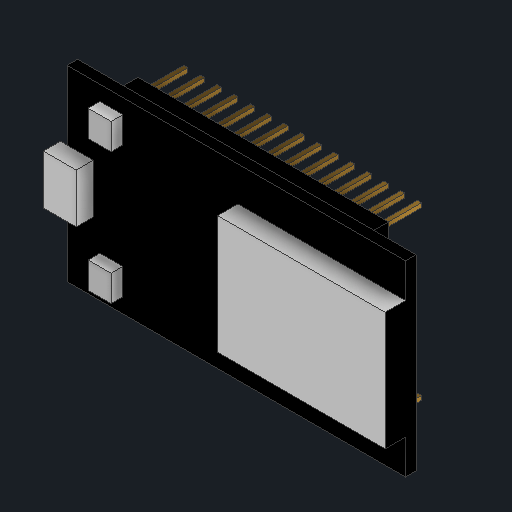
# Autodesk Inventor part: ESP32 DevKit 30-pin (Hosyond)
Saved by Autodesk Inventor 2027.2 (Build 312334000, 334)
## iProperties
Created: 2026-11-06
Part Number: ESP32 DevKit 30-pin (Hosyond)
Material: Generic
Description: Hosyond ESP-WROOM-32 30-pin devkit, simplified envelope (dims assumed, verify)
Document SubType Name: Modeling
Designer: isaac
Density: 1 g/cm^3
Appearance: Default
Author: isaac
Autodesk Inventor part; units mm, degrees
sketch "Sketch1" plane through (0, 0, 0) normal (0, 0, 1) x (1, 0, 0)
  line L0 (0, -14.25) -> (51.5, -14.25)
  line L1 (51.5, -14.25) -> (51.5, 14.25)
  line L2 (51.5, 14.25) -> (0, 14.25)
  line L3 (0, 14.25) -> (0, -14.25)
  constraints: 8 end point, 2 parallel, 1 horizontal, 1 perpendicular
extrude "PCB" add sketch "Sketch1" along normal blind 1.6
ref_plane "Work Plane1" through (0, 0, 1.6) normal (0, 0, 1) x (1, 0, 0)
sketch "Sketch2" plane through (0, 0, 1.6) normal (0, 0, 1) x (1, 0, 0)
  line L0 (26, -9) -> (51.5, -9)
  line L1 (51.5, -9) -> (51.5, 9)
  line L2 (51.5, 9) -> (26, 9)
  line L3 (26, 9) -> (26, -9)
  constraints: 8 end point, 2 parallel, 1 horizontal, 1 perpendicular
extrude "WROOM-32 module" add sketch "Sketch2" along normal blind 3.1
ref_plane "Work Plane2" through (0, 0, 1.6) normal (0, 0, 1) x (1, 0, 0)
sketch "Sketch3" plane through (0, 0, 1.6) normal (0, 0, 1) x (1, 0, 0)
  line L0 (-1, -3.75) -> (4, -3.75)
  line L1 (4, -3.75) -> (4, 3.75)
  line L2 (4, 3.75) -> (-1, 3.75)
  line L3 (-1, 3.75) -> (-1, -3.75)
  constraints: 8 end point, 2 parallel, 1 horizontal, 1 perpendicular
extrude "Micro-USB" add sketch "Sketch3" along normal blind 2.6
ref_plane "Work Plane3" through (0, 0, 1.6) normal (0, 0, 1) x (1, 0, 0)
sketch "Sketch4" plane through (0, 0, 1.6) normal (0, 0, 1) x (1, 0, 0)
  line L0 (5, -12) -> (8.5, -12)
  line L1 (8.5, -12) -> (8.5, -8)
  line L2 (8.5, -8) -> (5, -8)
  line L3 (5, -8) -> (5, -12)
  line L4 (5, 8) -> (8.5, 8)
  line L5 (8.5, 8) -> (8.5, 12)
  line L6 (8.5, 12) -> (5, 12)
  line L7 (5, 12) -> (5, 8)
  constraints: 16 end point, 4 parallel, 2 horizontal, 2 perpendicular
extrude "EN and BOOT buttons" add sketch "Sketch4" along normal blind 1.8
sketch "Sketch5" plane through (0, 0, 0) normal (0, 0, 1) x (1, 0, 0)
  line L0 (6.7, -13.97) -> (44.8, -13.97)
  line L1 (44.8, -13.97) -> (44.8, -11.43)
  line L2 (44.8, -11.43) -> (6.7, -11.43)
  line L3 (6.7, -11.43) -> (6.7, -13.97)
  line L4 (6.7, 11.43) -> (44.8, 11.43)
  line L5 (44.8, 11.43) -> (44.8, 13.97)
  line L6 (44.8, 13.97) -> (6.7, 13.97)
  line L7 (6.7, 13.97) -> (6.7, 11.43)
  constraints: 16 end point, 4 parallel, 2 horizontal, 2 perpendicular
extrude "Header plastic" add sketch "Sketch5" against normal blind 2.5
ref_plane "Work Plane4" through (0, 0, -2.5) normal (0, 0, 1) x (1, 0, 0)
sketch "Sketch6" plane through (0, 0, -2.5) normal (0, 0, 1) x (1, 0, 0)
  line L0 (7.65, -13.02) -> (8.29, -13.02)
  line L1 (8.29, -13.02) -> (8.29, -12.38)
  line L2 (8.29, -12.38) -> (7.65, -12.38)
  line L3 (7.65, -12.38) -> (7.65, -13.02)
  line L4 (10.19, -13.02) -> (10.83, -13.02)
  line L5 (10.83, -13.02) -> (10.83, -12.38)
  line L6 (10.83, -12.38) -> (10.19, -12.38)
  line L7 (10.19, -12.38) -> (10.19, -13.02)
  line L8 (12.73, -13.02) -> (13.37, -13.02)
  line L9 (13.37, -13.02) -> (13.37, -12.38)
  line L10 (13.37, -12.38) -> (12.73, -12.38)
  line L11 (12.73, -12.38) -> (12.73, -13.02)
  line L12 (15.27, -13.02) -> (15.91, -13.02)
  line L13 (15.91, -13.02) -> (15.91, -12.38)
  line L14 (15.91, -12.38) -> (15.27, -12.38)
  line L15 (15.27, -12.38) -> (15.27, -13.02)
  line L16 (17.81, -13.02) -> (18.45, -13.02)
  line L17 (18.45, -13.02) -> (18.45, -12.38)
  line L18 (18.45, -12.38) -> (17.81, -12.38)
  line L19 (17.81, -12.38) -> (17.81, -13.02)
  line L20 (20.35, -13.02) -> (20.99, -13.02)
  line L21 (20.99, -13.02) -> (20.99, -12.38)
  line L22 (20.99, -12.38) -> (20.35, -12.38)
  line L23 (20.35, -12.38) -> (20.35, -13.02)
  line L24 (22.89, -13.02) -> (23.53, -13.02)
  line L25 (23.53, -13.02) -> (23.53, -12.38)
  line L26 (23.53, -12.38) -> (22.89, -12.38)
  line L27 (22.89, -12.38) -> (22.89, -13.02)
  line L28 (25.43, -13.02) -> (26.07, -13.02)
  line L29 (26.07, -13.02) -> (26.07, -12.38)
  line L30 (26.07, -12.38) -> (25.43, -12.38)
  line L31 (25.43, -12.38) -> (25.43, -13.02)
  line L32 (27.97, -13.02) -> (28.61, -13.02)
  line L33 (28.61, -13.02) -> (28.61, -12.38)
  line L34 (28.61, -12.38) -> (27.97, -12.38)
  line L35 (27.97, -12.38) -> (27.97, -13.02)
  line L36 (30.51, -13.02) -> (31.15, -13.02)
  line L37 (31.15, -13.02) -> (31.15, -12.38)
  line L38 (31.15, -12.38) -> (30.51, -12.38)
  line L39 (30.51, -12.38) -> (30.51, -13.02)
  line L40 (33.05, -13.02) -> (33.69, -13.02)
  line L41 (33.69, -13.02) -> (33.69, -12.38)
  line L42 (33.69, -12.38) -> (33.05, -12.38)
  line L43 (33.05, -12.38) -> (33.05, -13.02)
  line L44 (35.59, -13.02) -> (36.23, -13.02)
  line L45 (36.23, -13.02) -> (36.23, -12.38)
  line L46 (36.23, -12.38) -> (35.59, -12.38)
  line L47 (35.59, -12.38) -> (35.59, -13.02)
  line L48 (38.13, -13.02) -> (38.77, -13.02)
  line L49 (38.77, -13.02) -> (38.77, -12.38)
  line L50 (38.77, -12.38) -> (38.13, -12.38)
  line L51 (38.13, -12.38) -> (38.13, -13.02)
  line L52 (40.67, -13.02) -> (41.31, -13.02)
  line L53 (41.31, -13.02) -> (41.31, -12.38)
  line L54 (41.31, -12.38) -> (40.67, -12.38)
  line L55 (40.67, -12.38) -> (40.67, -13.02)
  line L56 (43.21, -13.02) -> (43.85, -13.02)
  line L57 (43.85, -13.02) -> (43.85, -12.38)
  line L58 (43.85, -12.38) -> (43.21, -12.38)
  line L59 (43.21, -12.38) -> (43.21, -13.02)
  line L60 (7.65, 12.38) -> (8.29, 12.38)
  line L61 (8.29, 12.38) -> (8.29, 13.02)
  line L62 (8.29, 13.02) -> (7.65, 13.02)
  line L63 (7.65, 13.02) -> (7.65, 12.38)
  line L64 (10.19, 12.38) -> (10.83, 12.38)
  line L65 (10.83, 12.38) -> (10.83, 13.02)
  line L66 (10.83, 13.02) -> (10.19, 13.02)
  line L67 (10.19, 13.02) -> (10.19, 12.38)
  line L68 (12.73, 12.38) -> (13.37, 12.38)
  line L69 (13.37, 12.38) -> (13.37, 13.02)
  line L70 (13.37, 13.02) -> (12.73, 13.02)
  line L71 (12.73, 13.02) -> (12.73, 12.38)
  line L72 (15.27, 12.38) -> (15.91, 12.38)
  line L73 (15.91, 12.38) -> (15.91, 13.02)
  line L74 (15.91, 13.02) -> (15.27, 13.02)
  line L75 (15.27, 13.02) -> (15.27, 12.38)
  line L76 (17.81, 12.38) -> (18.45, 12.38)
  line L77 (18.45, 12.38) -> (18.45, 13.02)
  line L78 (18.45, 13.02) -> (17.81, 13.02)
  line L79 (17.81, 13.02) -> (17.81, 12.38)
  line L80 (20.35, 12.38) -> (20.99, 12.38)
  line L81 (20.99, 12.38) -> (20.99, 13.02)
  line L82 (20.99, 13.02) -> (20.35, 13.02)
  line L83 (20.35, 13.02) -> (20.35, 12.38)
  line L84 (22.89, 12.38) -> (23.53, 12.38)
  line L85 (23.53, 12.38) -> (23.53, 13.02)
  line L86 (23.53, 13.02) -> (22.89, 13.02)
  line L87 (22.89, 13.02) -> (22.89, 12.38)
  line L88 (25.43, 12.38) -> (26.07, 12.38)
  line L89 (26.07, 12.38) -> (26.07, 13.02)
  line L90 (26.07, 13.02) -> (25.43, 13.02)
  line L91 (25.43, 13.02) -> (25.43, 12.38)
  line L92 (27.97, 12.38) -> (28.61, 12.38)
  line L93 (28.61, 12.38) -> (28.61, 13.02)
  line L94 (28.61, 13.02) -> (27.97, 13.02)
  line L95 (27.97, 13.02) -> (27.97, 12.38)
  line L96 (30.51, 12.38) -> (31.15, 12.38)
  line L97 (31.15, 12.38) -> (31.15, 13.02)
  line L98 (31.15, 13.02) -> (30.51, 13.02)
  line L99 (30.51, 13.02) -> (30.51, 12.38)
  line L100 (33.05, 12.38) -> (33.69, 12.38)
  line L101 (33.69, 12.38) -> (33.69, 13.02)
  line L102 (33.69, 13.02) -> (33.05, 13.02)
  line L103 (33.05, 13.02) -> (33.05, 12.38)
  line L104 (35.59, 12.38) -> (36.23, 12.38)
  line L105 (36.23, 12.38) -> (36.23, 13.02)
  line L106 (36.23, 13.02) -> (35.59, 13.02)
  line L107 (35.59, 13.02) -> (35.59, 12.38)
  line L108 (38.13, 12.38) -> (38.77, 12.38)
  line L109 (38.77, 12.38) -> (38.77, 13.02)
  line L110 (38.77, 13.02) -> (38.13, 13.02)
  line L111 (38.13, 13.02) -> (38.13, 12.38)
  line L112 (40.67, 12.38) -> (41.31, 12.38)
  line L113 (41.31, 12.38) -> (41.31, 13.02)
  line L114 (41.31, 13.02) -> (40.67, 13.02)
  line L115 (40.67, 13.02) -> (40.67, 12.38)
  line L116 (43.21, 12.38) -> (43.85, 12.38)
  line L117 (43.85, 12.38) -> (43.85, 13.02)
  line L118 (43.85, 13.02) -> (43.21, 13.02)
  line L119 (43.21, 13.02) -> (43.21, 12.38)
  constraints: 240 end point, 60 parallel, 30 horizontal, 30 perpendicular
extrude "Pins" add sketch "Sketch6" against normal blind 6
body "Solid1"
